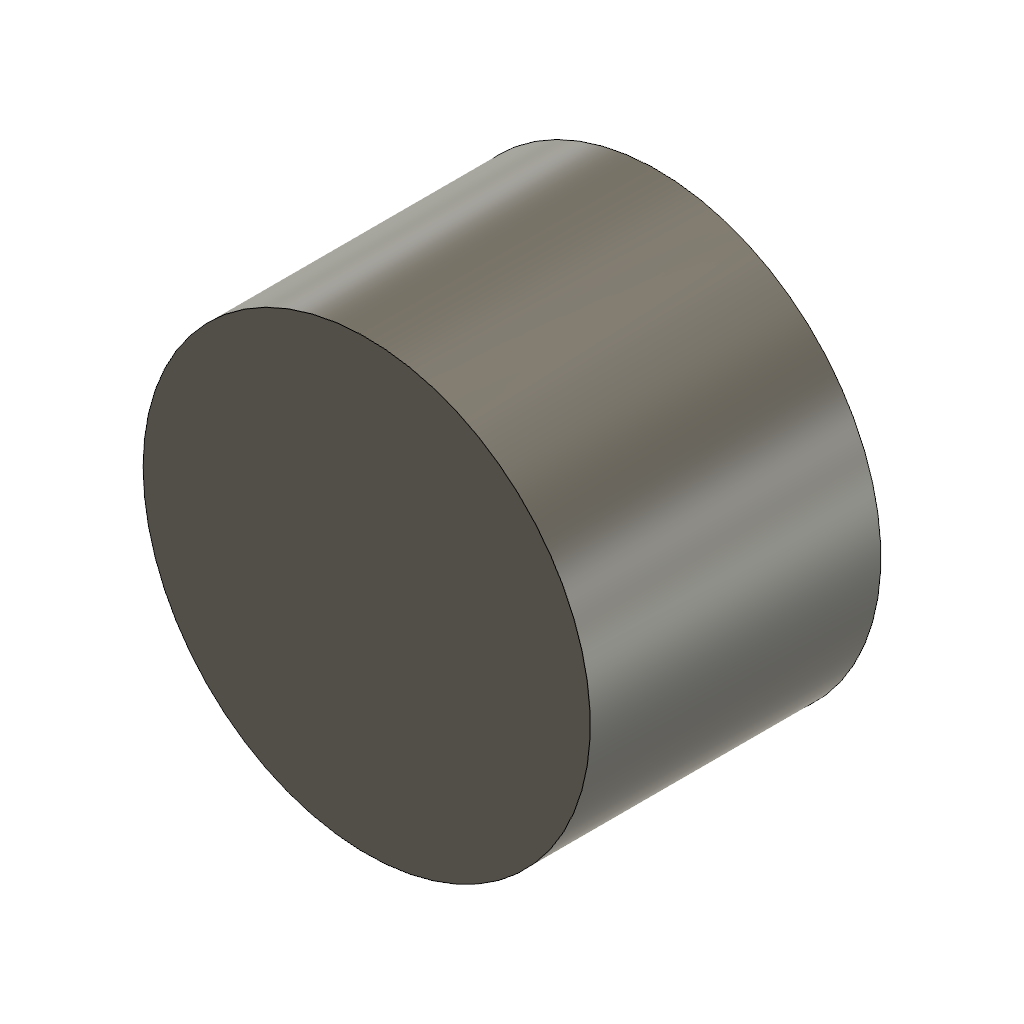
depth13 (Autodesk Fusion 360 design; units mm, degrees)
part number: 2026-10-20-16-37-55-984
Autodesk Fusion 360 part; units mm, degrees
sketch "Sketch1" plane through (0, 0, 0) normal (0, 0, 1) x (1, 0, 0)
  circle A0 centre (0, 0) radius 10
extrude "ReferenceExtrusion" add sketch "Sketch1" along normal blind 13
